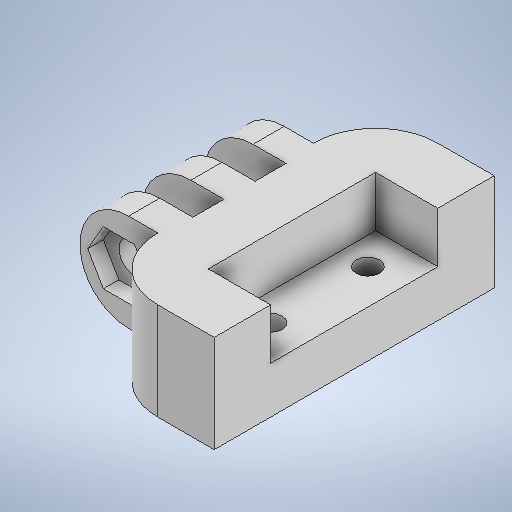
# Autodesk Inventor part: realsense_d405_mounting
Saved by Autodesk Inventor 2026.1 (Build 301233020, 233B)
## iProperties
Created: 2025-11-04
Part Number: realsense_d405_mounting
Material: Generic
Document SubType Name: Modeling
Designer: mobimobi
Density: 1 g/cm^3
Appearance: Default
Author: mobimobi
Autodesk Inventor part; units mm, degrees
ref_plane "YZ Plane" through (0, 0, 0) normal (1, 0, 0) x (0, 1, 0)
ref_plane "XZ Plane" through (0, 0, 0) normal (0, 1, 0) x (-1, 0, 0)
ref_plane "XY Plane" through (0, 0, 0) normal (0, 0, 1) x (1, 0, 0)
sketch "Sketch1" plane through (0, 0, 0) normal (0, 1, 0) x (-1, 0, 0)
  line L0 (0, 0) -> (-36, 0)
  line L1 (-36, 0) -> (-36, -36)
  line L2 (-36, -36) -> (0, -36)
  line L3 (0, -36) -> (0, 0)
  line L4 (0, -18) -> (-36, -18)
  line L5 (-18, -18) -> (-18, -8)
  line L6 (-18, -8) -> (-18, -18)
  line L7 (-18, -18) -> (-18, -28)
  circle A0 centre (-18, -8) radius 1.5
  circle A1 centre (-18, -28) radius 1.5
  line L8 (-36, -36) -> (-39, -36)
  line L9 (-39, -36) -> (-39, 0)
  line L10 (-39, 0) -> (-36, 0)
  line L11 (-36, 0) -> (-36, -36)
  dimension "d0" = 36
  dimension "d1" = 36
  dimension "d2" = 10
  dimension "d3" = 10
  dimension "d4" = 3
  dimension "d5" = 3
  dimension "d14" = 3
  constraints: 24 end point, 5 equal length, 3 midpoint, 2 centre point, 2 coincident, 2 horizontal, 2 perpendicular, 1 point on line, 1 vertical
  measures "d0" distance of L2.end L1.end
  measures "d1" distance of L1.end L0.end
  measures "d2" distance of L5.start L5.end
  measures "d3" distance of L5.start L7.end
  measures "d4" diameter of A0
  measures "d5" diameter of A1
  measures "d14" distance of L9.end L10.end
extrude "Extrusion3" add sketch "Sketch1" along normal blind 5
sketch "Sketch3" plane through (0, 0, 0) normal (0, -1, 0) x (1, 0, 0)
  line L0 (39, 0) -> (39, -36) projected
  line L1 (39, -36) -> (44, -36)
  line L2 (44, -36) -> (44, 0)
  line L3 (44, 0) -> (39, 0)
  line L4 (39, 0) -> (39, -36)
  point P0 (0, 0)
  dimension "d17" = 5
  constraints: 8 end point, 2 parallel, 1 horizontal, 1 perpendicular
  measures "d17" distance of L3.end L2.end
extrude "Extrusion4" add sketch "Sketch3" against normal blind 11.5
sketch "Sketch5" plane through (0, 0, 0) normal (0, -1, 0) x (1, 0, 0)
  line L0 (44, 0) -> (44, -36) projected
  line L1 (44, -36) -> (44, 0)
  line L2 (44, -7.25) -> (44, -28.75)
  line L3 (44, -28.75) -> (52, -28.75)
  line L4 (52, -28.75) -> (52, -7.25)
  line L5 (52, -7.25) -> (44, -7.25)
  line L6 (44, -7.25) -> (44, -28.75)
  line L7 (44, -36) -> (52, -36)
  line L8 (52, -36) -> (52, 0)
  line L9 (52, 0) -> (44, 0)
  line L10 (44, 0) -> (44, -36)
  point P0 (0, 0)
  point P1 (44, -18)
  dimension "d20" = 21.5
  dimension "d21" = 8
  constraints: 20 end point, 5 equal length, 2 horizontal, 2 midpoint, 2 perpendicular, 1 point on line
  measures "d20" distance of L2.start L2.end
  measures "d21" distance of L5.end L4.end
extrude "Extrusion5" add sketch "Sketch5" against normal blind 11.5 contours L9 L8 L5 L0 | L3 L8 L7 L0
sketch "Sketch6" plane through (0, 0, 0) normal (0, -1, 0) x (1, 0, 0)
  line L0 (52, -28.75) -> (44, -28.75) projected
  line L1 (52, -7.25) -> (52, 0) projected
  line L2 (44, -28.75) -> (52, -28.75)
  line L3 (52, -28.75) -> (52, -7.25)
  line L4 (52, -7.25) -> (44, -7.25)
  line L5 (44, -7.25) -> (44, -28.75)
  line L6 (44, -28.75) -> (47.5, -28.75)
  line L7 (47.5, -28.75) -> (47.5, -24.25)
  line L8 (47.5, -24.25) -> (44, -24.25)
  line L9 (44, -24.25) -> (44, -28.75)
  line L10 (44, -7.25) -> (47.5, -7.25)
  line L11 (47.5, -7.25) -> (47.5, -11.75)
  line L12 (47.5, -11.75) -> (44, -11.75)
  line L13 (44, -11.75) -> (44, -7.25)
  circle A0 centre (47.5, -24.25) radius 1.5
  circle A1 centre (47.5, -11.75) radius 1.5
  point P0 (0, 0)
  dimension "d24" = 3.5
  dimension "d25" = 4.5
  dimension "d26" = 3.5
  dimension "d27" = 4.5
  dimension "d28" = 3
  dimension "d29" = 3
  constraints: 24 end point, 6 parallel, 3 horizontal, 3 perpendicular, 2 centre point, 2 coincident
  measures "d24" distance of L8.end L7.end
  measures "d25" distance of L7.end L6.end
  measures "d26" distance of L11.end L12.end
  measures "d27" distance of L10.end L11.end
  measures "d28" diameter of A0
  measures "d29" diameter of A1
extrude "Extrusion6" add sketch "Sketch6" against normal blind 5 contours L0 L7 A0 L8 L5 L12 A1 L11 L4 L3 | L0 L5 L8 A0 L7 | L11 A1 L12 L5 L4
sketch "Sketch8" plane through (0, 0, 0) normal (0, -1, 0) x (1, 0, 0)
  line L0 (39, -36) -> (0, -36) projected
  line L1 (39, 0) -> (52, 0) projected
  line L2 (0, -36) -> (52, -36)
  line L3 (52, -36) -> (52, 0)
  line L4 (52, 0) -> (0, 0)
  line L5 (0, 0) -> (0, -36)
  circle A0 centre (18, -28) radius 1.5 projected
  circle A1 centre (18, -28) radius 1.5
  circle A2 centre (18, -8) radius 1.5 projected
  circle A3 centre (18, -8) radius 1.5
  circle A4 centre (47.5, -24.25) radius 1.5 projected
  circle A5 centre (47.5, -24.25) radius 1.5
  circle A6 centre (47.5, -11.75) radius 1.5 projected
  circle A7 centre (47.5, -11.75) radius 1.5
  constraints: 8 end point, 4 centre point, 4 coincident, 2 parallel, 1 horizontal, 1 perpendicular
extrude "Extrusion7" add sketch "Sketch8" along normal blind 1
sketch "Sketch9" plane through (0, 5, 0) normal (0, 1, 0) x (1, 0, 0)
  line L0 (39, 0) -> (39, 36) projected
  line L1 (0, 0) -> (39, 0)
  line L2 (39, 0) -> (39, 36)
  line L3 (39, 36) -> (0, 36)
  line L4 (0, 36) -> (0, 0)
  circle A0 centre (18, 8) radius 1.5 projected
  circle A1 centre (18, 8) radius 1.5
  circle A2 centre (18, 28) radius 1.5 projected
  circle A3 centre (18, 28) radius 1.5
  constraints: 8 end point, 2 centre point, 2 coincident, 2 parallel, 1 horizontal, 1 perpendicular
extrude "Extrusion8" add sketch "Sketch9" along normal blind 6.5
sketch "Sketch10" plane through (0, 11.5, 0) normal (0, 1, 0) x (1, 0, 0)
  line L0 (44, 7.25) -> (44, 28.75) projected
  line L1 (0, 36) -> (52, 36) projected
  line L2 (44, 28.75) -> (52, 28.75)
  line L3 (52, 28.75) -> (52, 36)
  line L4 (52, 36) -> (44, 36)
  line L5 (44, 36) -> (44, 28.75)
  line L6 (52, 0) -> (0, 0) projected
  line L7 (44, 36) -> (26.75, 36)
  line L8 (26.75, 36) -> (26.75, 0)
  line L9 (26.75, 0) -> (44, 0)
  line L10 (44, 0) -> (44, 36)
  line L11 (26.75, 0) -> (12.75, 0)
  line L12 (12.75, 0) -> (12.75, 36)
  line L13 (12.75, 36) -> (26.75, 36)
  line L14 (26.75, 36) -> (26.75, 0)
  line L15 (44, 0) -> (36.75, 0)
  line L16 (36.75, 0) -> (36.75, 36)
  line L17 (36.75, 36) -> (44, 36)
  line L18 (44, 36) -> (44, 0)
  line L19 (26.75, 0) -> (36.75, 0)
  line L20 (36.75, 0) -> (36.75, 36)
  line L21 (36.75, 36) -> (26.75, 36)
  line L22 (26.75, 36) -> (26.75, 0)
  line L23 (26.75, 20) -> (36.75, 20)
  line L24 (36.75, 20) -> (36.75, 16)
  line L25 (36.75, 16) -> (26.75, 16)
  line L26 (26.75, 16) -> (26.75, 20)
  line L27 (26.75, 20) -> (36.75, 16) construction
  line L28 (36.75, 20) -> (26.75, 16) construction
  line L29 (26.75, 16) -> (36.75, 16)
  line L30 (36.75, 16) -> (36.75, 12)
  line L31 (36.75, 12) -> (26.75, 12)
  line L32 (26.75, 12) -> (26.75, 16)
  line L33 (26.75, 20) -> (36.75, 20)
  line L34 (36.75, 20) -> (36.75, 24)
  line L35 (36.75, 24) -> (26.75, 24)
  line L36 (26.75, 24) -> (26.75, 20)
  line L37 (26.75, 12) -> (36.75, 12)
  line L38 (36.75, 12) -> (36.75, 8)
  line L39 (36.75, 8) -> (26.75, 8)
  line L40 (26.75, 8) -> (26.75, 12)
  line L41 (26.75, 24) -> (36.75, 24)
  line L42 (36.75, 24) -> (36.75, 28)
  line L43 (36.75, 28) -> (26.75, 28)
  line L44 (26.75, 28) -> (26.75, 24)
  line L45 (0, 0) -> (0, 36) projected
  line L46 (0, 0) -> (12.75, 0)
  line L47 (12.75, 0) -> (12.75, 36)
  line L48 (12.75, 36) -> (0, 36)
  line L49 (0, 36) -> (0, 0)
  point P0 (31.75, 18)
  dimension "d36" = 17.25
  dimension "d37" = 14
  dimension "d38" = 7.25
  dimension "d39" = 10
  dimension "d40" = 4
  dimension "d41" = 4
  dimension "d42" = 4
  dimension "d43" = 4
  dimension "d44" = 4
  constraints: 92 end point, 22 parallel, 11 horizontal, 11 perpendicular, 7 point on line, 2 midpoint
  measures "d36" distance of L9.end L8.end
  measures "d37" distance of L12.end L13.end
  measures "d38" distance of L16.end L17.end
  measures "d39" distance of L24.end L25.end
  measures "d40" distance of L23.end L24.end
  measures "d41" distance of L29.end L30.end
  measures "d42" distance of L34.end L33.end
  measures "d43" distance of L37.end L38.end
  measures "d44" distance of L42.end L41.end
extrude "Extrusion9" cut sketch "Sketch10" against normal blind 23 contours L6 L8 L39 L16 | L16 L43 L8 L1 | L6 L12 L1 L8 | L6 L45 L1 L12 | L31 L8 L25 L16 | L16 L23 L8 L35
sketch "Sketch11" plane through (36.75, 11.5, -28) normal (0, 0, -1) x (-1, 0, 0)
  line L0 (10, 0) -> (10, -12.5) projected
  line L1 (10, -12.5) -> (0, -12.5) projected
  line L2 (10, 0) -> (0, 0)
  line L3 (0, 0) -> (0, -12.5)
  line L4 (0, -12.5) -> (10, -12.5)
  line L5 (10, -12.5) -> (10, 0)
  line L6 (10, 0) -> (0, -12.5)
  line L7 (10, -12.5) -> (0, 0)
  circle A0 centre (5, -6.25) radius 2
  point P0 (36.75, -11.5)
  dimension "d47" = 4
  constraints: 12 end point, 2 parallel, 1 centre point, 1 horizontal, 1 midpoint, 1 perpendicular
  measures "d47" diameter of A0
extrude "Extrusion10" cut sketch "Sketch11" against normal blind 23 contours A0 L7 L6 | L6 L7 A0 | A0 L6 L7 | L7 L6 A0
sketch "Sketch12" plane through (36.75, 11.5, -28) normal (0, 0, -1) x (-1, 0, 0)
  circle A0 centre (5, -6.25) radius 2 projected
  circle A1 centre (5, -6.25) radius 3.5
  point P0 (36.75, -11.5)
  dimension "d50" = 7
  constraints: 1 centre point, 1 coincident
  measures "d50" diameter of A1
extrude "Extrusion11" cut sketch "Sketch12" against normal blind 2
sketch "Sketch13" plane through (26.75, 11.5, -8) normal (0, 0, 1) x (1, 0, 0)
  circle A0 centre (5, -6.25) radius 2 projected
  line L0 (5, -2.786) -> (5, -9.714)
  line L1 (5, -9.714) -> (3, -9.714)
  line L2 (3, -9.714) -> (1, -6.2499)
  line L3 (1, -6.2499) -> (3, -2.7858)
  line L4 (3, -2.7858) -> (5, -2.7858)
  line L5 (5, -2.7858) -> (7, -2.7858)
  line L6 (7, -2.7858) -> (9, -6.2499)
  line L7 (9, -6.2499) -> (7, -9.714)
  circle A1 centre (5, -6.25) radius 3.5 projected
  line L8 (7, -9.714) -> (5, -9.714)
  point P0 (-26.75, -11.5)
  dimension "d53" = 6.928
  dimension "d54" = 2
  dimension "d55" = 4
  dimension "d56" = 120
  dimension "d57" = 4
  dimension "d58" = 120
  dimension "d59" = 2
  dimension "d60" = 120
  dimension "d61" = 2
  dimension "d62" = 180
  dimension "d63" = 4
  dimension "d64" = 120
  dimension "d65" = 4
  dimension "d66" = 120
  constraints: 18 end point, 4 equal length, 1 horizontal, 1 midpoint, 1 vertical
  measures "d53" distance of L0.start L0.end
  measures "d54" distance of L0.end L1.end
  measures "d55" distance of L1.end L2.end
  measures "d56" angle of L1 L2
  measures "d57" distance of L2.end L3.end
  measures "d58" angle of L2 L3
  measures "d59" distance of L3.end L4.end
  measures "d60" angle of L3 L4
  measures "d61" distance of L4.end L5.end
  measures "d62" angle of L5 L4
  measures "d63" distance of L5.end L6.end
  measures "d64" angle of L5 L6
  measures "d65" distance of L6.end L7.end
  measures "d66" angle of L6 L7
extrude "Extrusion12" cut sketch "Sketch13" against normal blind 2 contours A0 L0 L5 A1 L6 L7 L8 | A0 L0 L1 A1 L2 L3 L4 | A1 L3 L4 | L5 L6 A1 | L1 L2 A1 | A1 L7 L8 | A1 L2 L3 | L6 L7 A1
fillet "Fillet1" radius 6.25 6 edges at (26.75, -1, -26) (26.75, -1, -18) (26.75, -1, -10) (26.75, 11.5, -26) (26.75, 11.5, -18) (26.75, 11.5, -10)
fillet "Fillet2" radius 8 2 edges at (36.75, 5.25, -36) (36.75, 5.25, 0)
sketch "Sketch14" plane through (36.75, 11.5, -16) normal (-1, 0, 0) x (0, 0, 1)
  line L0 (4, 0) -> (4, -12.5) projected
  line L1 (0, 0) -> (0, -12.5) projected
  line L2 (4, -12.5) -> (0, -12.5)
  line L3 (0, -12.5) -> (0, 0)
  line L4 (0, 0) -> (4, 0)
  line L5 (4, 0) -> (4, -12.5)
  line L6 (-4, 0) -> (-4, -12.5) projected
  line L7 (-8, 0) -> (-8, -12.5) projected
  line L8 (-4, -12.5) -> (-8, -12.5)
  line L9 (-8, -12.5) -> (-8, 0)
  line L10 (-8, 0) -> (-4, 0)
  line L11 (-4, 0) -> (-4, -12.5)
  point P0 (16, -11.5)
  constraints: 16 end point, 4 parallel, 2 horizontal, 2 perpendicular
extrude "Extrusion13" cut sketch "Sketch14" against normal blind 0.5
body "Solid2"
